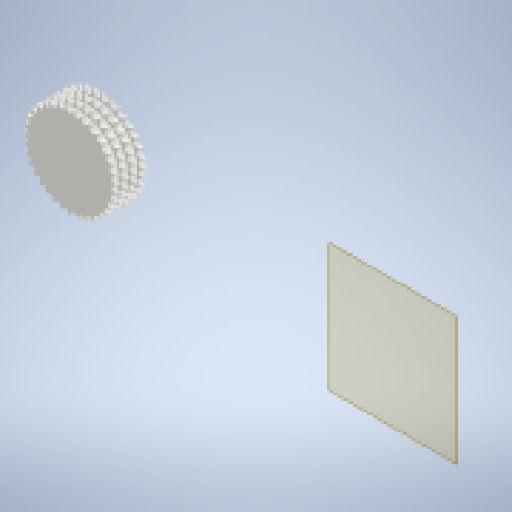
# Autodesk Inventor part: Rueda dentada de cadena de rodillos1
Saved by Autodesk Inventor 2024 (Build 280153000, 153)
## iProperties
CustomPartVersion: 1
Created: 2024-09-19
Part Number: Rueda dentada de cadena de rodillos1
Material: Steel
Document SubType Name: Modeling
Designer: aulac205
Density: 1 g/cm^3
Appearance: Steel
Author: aulac205
Autodesk Inventor part; units mm, degrees
ref_plane "YZ Plane" through (0, 0, 0) normal (1, 0, 0) x (0, 1, 0)
ref_plane "XZ Plane" through (0, 0, 0) normal (0, 1, 0) x (-1, 0, 0)
sketch "Perfil de diente teórico" plane through (0, 0, 0) normal (0, 0, 1) x (1, 0, 0)
  circle A0 centre (0, 0) radius 70.8395 construction
  line L0 (0, 0) -> (0, 70.8395) construction
  line L1 (0, 0) -> (12.6489, 69.701) construction
  circle A1 centre (0, 0) radius 74.3643
  arc A2 (-3.2228, 68.436) -> (3.2228, 68.436) centre (0, 70.8395) ccw
  line L2 (0, 70.8395) -> (12.6489, 69.701) construction
  line L3 (0, 70.8395) -> (5.0822, 74.6296) construction
  line L4 (5.0822, 74.6296) -> (-4.6336, 71.0328) construction
  arc A3 (6.232, 74.1027) -> (5.0202, 72.0772) centre (11.0501, 69.8449) ccw
  arc A4 (-5.0202, 72.0772) -> (-6.232, 74.1027) centre (-11.0501, 69.8449) ccw
  line L5 (-11.0501, 69.8449) -> (-5.0202, 72.0772) construction
  arc A5 (-4.6336, 71.0328) -> (-3.2228, 68.436) centre (5.0822, 74.6296) ccw
  line L6 (-4.6336, 71.0328) -> (-5.0202, 72.0772)
  arc A6 (3.2228, 68.436) -> (4.6336, 71.0328) centre (-5.0822, 74.6296) ccw
  line L7 (5.0202, 72.0772) -> (4.6336, 71.0328)
  line L8 (0, 0) -> (6.666, 74.0649) construction
  point P0 (6.3244, 70.2702)
  dimension "d0" = 141.6789
  dimension "d2" = 10.286
  dimension "d3" = 4.0203
  dimension "d10" = 126.714
  dimension "d11" = 16.4
  dimension "d12" = 6.3398
  dimension "d13" = 10.3602
  dimension "d14" = 11.0947
  dimension "d23" = 3.81
  constraints: 18 end point, 15 point on circle, 7 centre point, 3 coincident, 3 point on line, 3 symmetric about line, 3 tangent, 1 equal radius, 1 midpoint, 1 parallel, 1 vertical, 1 other
  measures "d0" diameter of A0
  measures "d2" angle of L1 L0
  measures "d3" radius of A2
  measures "d10" angle of L3 L0
  measures "d11" angle of L4 L3
  measures "d12" distance of L2.start L3.end
  measures "d13" distance of L3.end L4.end
  measures "d14" distance of A3.centre L0.end
  measures "d23" distance from line of L8.end L2
sketch "Perfil de diente" plane through (0, 0, 0) normal (0, 0, 1) x (1, 0, 0)
  circle A0 centre (0, 0) radius 74.3643 projected
  line L0 (0, 0) -> (0, 70.8395) construction
  line L1 (0, 70.8395) -> (3.7461, 69.38) construction
  arc A1 (-3.7461, 69.38) -> (3.7461, 69.38) centre (0, 70.8395) ccw
  line L2 (-3.7461, 69.38) -> (0, 70.8395) construction
  arc A2 (-3.7461, 69.38) -> (-6.0142, 74.1207) centre (-36.5318, 56.6068) ccw
  arc A3 (6.0142, 74.1207) -> (3.7461, 69.38) centre (36.5318, 56.6068) ccw
  dimension "d44" = 137.429
  dimension "d45" = 4.0203
  dimension "d46" = 35.1861
  constraints: 8 point on circle, 7 end point, 3 centre point, 2 tangent, 1 coincident, 1 equal radius, 1 symmetric about line, 1 vertical
  measures "d44" angle of L1 L2
  measures "d45" radius of A1
  measures "d46" radius of A3
sketch "Perfil de sección" plane through (0, 0, 0) normal (1, 0, 0) x (0, 1, 0)
  line L0 (74.3643, 0) -> (-74.3643, 0) projected
  line L1 (63.3153, 46.6893) -> (-63.3153, 46.6893)
  line L2 (-63.3153, 46.6893) -> (-63.3153, -3.5601)
  line L3 (-63.3153, -3.5601) -> (63.3153, -3.5601)
  line L4 (63.3153, -3.5601) -> (63.3153, 46.6893)
  line L5 (63.3153, 3.5601) -> (74.3643, 3.5601) construction
  line L6 (74.3643, 3.5601) -> (74.3643, -3.5601) construction
  line L7 (74.3643, -3.5601) -> (63.3153, -3.5601) construction
  line L8 (63.3153, -3.5601) -> (63.3153, 3.5601)
  arc A0 (74.3643, 1.9726) -> (68.0127, 3.5601) centre (68.0127, -9.94) ccw
  arc A1 (68.0127, -3.5601) -> (74.3643, -1.9726) centre (68.0127, 9.94) ccw
  line L9 (68.0127, 3.5601) -> (0, 3.5601)
  line L10 (0, 3.5601) -> (0, -3.5601)
  line L11 (0, -3.5601) -> (68.0127, -3.5601)
  line L12 (0, 46.6893) -> (0, -3.5601)
  line L13 (74.3643, 1.9726) -> (74.3643, -1.9726)
  point P0 (0, 0)
  point P1 (0, 0)
  dimension "d30" = 7.1201
  dimension "d31" = 126.6306
  dimension "d32" = 50.2493
  dimension "d33" = 1.5875
  dimension "d34" = 13.5001
  dimension "d43" = 3.5601
  constraints: 26 end point, 6 midpoint, 5 perpendicular, 4 parallel, 4 point on circle, 4 point on line, 3 symmetric about line, 2 centre point, 2 horizontal, 2 tangent, 1 collinear, 1 other
  measures "d30" distance between parallel lines of L7 L5
  measures "d31" distance between parallel lines of L2 L4
  measures "d32" distance between parallel lines of L3 L1
  measures "d33" distance from line of L13.start L5
  measures "d34" radius of A0
  measures "d43" distance between parallel lines of L3 L0
revolve "Cubierta" add sketch "Perfil de sección" angle 360 about axis through (0, 0, 46.6893) along (0, 0, -1) contours L10 L3 L2 L0 | L0 L2 L1 L12 L10
revolve "Ramal" add sketch "Perfil de sección" angle 360 about axis through (0, 0, 46.6893) along (0, 0, -1) contours L13 A1 L11 L4 L0 | L0 L4 L9 A0 L13 | L4 L3 L10 L0 | L0 L10 L9 L4
pattern_linear "Patrón de ramal" count 4 spacing 14.3764 along (0, 0, 1) of "Ramal"
extrude "Diente teórico" cut sketch "Perfil de diente teórico" along normal through all both and the other way through all contours A3 L7 A6 A2 A5 L6 A4 A1 picked at (-0.6932, 70.4024)
extrude "Diente" [suppressed]
pattern_circular "Patrón de diente" count 35 over 360 about axis through (0, 0, -10) along (0, 0, 1) of "Diente teórico"
ref_plane "Plano síncrono" through (0, 70.8395, 0) normal (1, 0, 0) x (0, 1, 0)
ref_plane "Plano de trabajo3" through (513.7276, -36.9051, 46.6893) normal (0, 0, 1) x (1, 0, 0)
equation "\"d3\" = 0.5 * da_Dr + da_SC"
equation "\"d12\" = 0.8 * da_Dr"
equation "\"d13\" = 1.3 * da_Dr + da_SC"
equation "\"d14\" = 1.4 * da_Dr"
equation "\"d23\" = da_Ha"
equation "\"d44\" = da_Alfa"
equation "\"d45\" = da_Ri"
equation "\"d46\" = da_Re"
equation "\"d30\" = da_Bf"
equation "\"d31\" = da_Ds"
equation "\"d32\" = da_Bs"
equation "\"d33\" = da_Ba"
equation "\"d34\" = da_Rx"
equation "\"d40\" = da_pt"
equation "\"form_type\" = 0"
equation "\"da_p\" = 12.7"
equation "\"da_Dr\" = 7.9248"
equation "\"da_SC\" = 0.05791"
equation "\"da_Ha\" = 3.81"
equation "\"da_pt\" = 14.3764"
equation "\"da_Bf\" = 7.12013"
equation "\"da_Ba\" = 1.5875"
equation "\"da_Rx\" = 13.5001"
equation "\"da_Ra\" = 0.508"
equation "\"da_Bs\" = 50.24933"
equation "\"da_Ds\" = 126.63056"
equation "\"da_Re\" = 35.18611"
equation "\"da_Ri\" = 4.02031"
equation "\"da_Alfa\" = 137.429deg"
body "Solid1"
